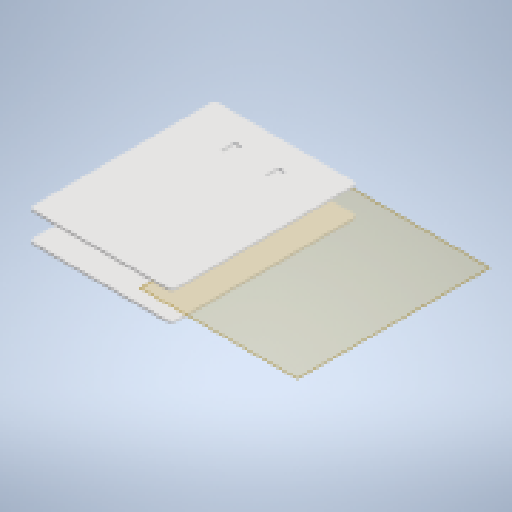
# Autodesk Inventor part: meio
Saved by Autodesk Inventor 2025.2 (Build 292293000, 293)
## iProperties
Created: 2026-05-27
Part Number: meio
Material: Generic
Document SubType Name: Modeling
Designer: joaoc
Density: 1 g/cm^3
Appearance: Default
Author: joaoc
Autodesk Inventor part; units mm, degrees
ref_plane "YZ Plane" through (0, 0, 0) normal (1, 0, 0) x (0, 1, 0)
ref_plane "XZ Plane" through (0, 0, 0) normal (0, 1, 0) x (-1, 0, 0)
ref_plane "XY Plane" through (0, 0, 0) normal (0, 0, 1) x (1, 0, 0)
sketch "Sketch1" plane through (0, 0, 0) normal (0, 1, 0) x (-1, 0, 0)
  line L0 (0, 0) -> (0, 13.2)
  arc A0 (13.2, 26.4) -> (0, 13.2) centre (13.2, 13.2) ccw
  line L1 (13.2, 26.4) -> (386.8, 26.4)
  arc A1 (400, 13.2) -> (386.8, 26.4) centre (386.8, 13.2) ccw
  line L2 (400, 13.2) -> (400, 0)
  line L3 (0, -335.4) -> (0, -131.8)
  line L4 (400, -467.2) -> (400, -480.4)
  arc A2 (386.8, -493.6) -> (400, -480.4) centre (386.8, -480.4) ccw
  line L5 (386.8, -493.6) -> (13.2, -493.6)
  arc A3 (0, -480.4) -> (13.2, -493.6) centre (13.2, -480.4) ccw
  line L6 (0, -480.4) -> (0, -467.2)
  line L7 (400, -131.8) -> (400, -335.4)
  line L8 (190, -45.9) -> (210, -45.9)
  line L9 (210, -45.9) -> (210, -85.9)
  line L10 (210, -85.9) -> (190, -85.9)
  line L11 (190, -85.9) -> (190, -45.9)
  line L12 (128.7, -381.3) -> (148.7, -381.3)
  line L13 (148.7, -381.3) -> (148.7, -421.3)
  line L14 (148.7, -421.3) -> (128.7, -421.3)
  line L15 (128.7, -421.3) -> (128.7, -381.3)
  line L16 (251.3, -381.3) -> (271.3, -381.3)
  line L17 (271.3, -381.3) -> (271.3, -421.3)
  line L18 (271.3, -421.3) -> (251.3, -421.3)
  line L19 (251.3, -421.3) -> (251.3, -381.3)
  line L20 (400, -467.2) -> (400, -335.4)
  line L21 (400, -131.8) -> (400, 0)
  line L22 (0, 0) -> (0, -131.8)
  line L23 (0, -335.4) -> (0, -467.2)
  point P0 (0, -480.4)
  point P1 (386.8, -493.6)
  point P2 (400, 13.2)
  point P3 (13.2, 26.4)
  constraints: 48 end point, 8 point on circle, 4 centre point, 3 equal length
extrude "Extrusion1" add sketch "Sketch1" along normal blind 6
ref_plane "Work Plane1" through (0, 79, 0) normal (0, 1, 0) x (1, 0, 0)
sketch "Sketch2" plane through (0, 79, 0) normal (0, 1, 0) x (1, 0, 0)
  line L0 (0, 0) -> (0, -13.2)
  arc A0 (-13.2, -26.4) -> (0, -13.2) centre (-13.2, -13.2) ccw
  line L1 (-13.2, -26.4) -> (-386.8, -26.4)
  arc A1 (-400, -13.2) -> (-386.8, -26.4) centre (-386.8, -13.2) ccw
  line L2 (-400, -13.2) -> (-400, 0)
  line L3 (0, 335.4) -> (0, 131.8)
  line L4 (-400, 467.2) -> (-400, 480.4)
  arc A2 (-386.8, 493.6) -> (-400, 480.4) centre (-386.8, 480.4) ccw
  line L5 (-386.8, 493.6) -> (-13.2, 493.6)
  arc A3 (0, 480.4) -> (-13.2, 493.6) centre (-13.2, 480.4) ccw
  line L6 (0, 480.4) -> (0, 467.2)
  line L7 (-400, 131.8) -> (-400, 335.4)
  line L8 (-190, 45.9) -> (-210, 45.9)
  line L9 (-210, 45.9) -> (-210, 85.9)
  line L10 (-210, 85.9) -> (-190, 85.9)
  line L11 (-190, 85.9) -> (-190, 45.9)
  line L12 (-400, 0) -> (-400, 131.8)
  line L13 (-400, 335.4) -> (-400, 467.2)
  line L14 (0, 335.4) -> (0, 467.2)
  line L15 (0, 0) -> (0, 131.8)
  point P0 (-400, -13.2)
  point P1 (-400, 480.4)
  point P2 (0, 480.4)
  point P3 (-386.8, 493.6)
  point P4 (-400, -13.2)
  point P5 (-13.2, -26.4)
  constraints: 32 end point, 8 point on circle, 4 centre point, 2 collinear, 1 parallel, 1 vertical
extrude "Extrusion2" add sketch "Sketch2" along normal blind 6
body "Solid1"
